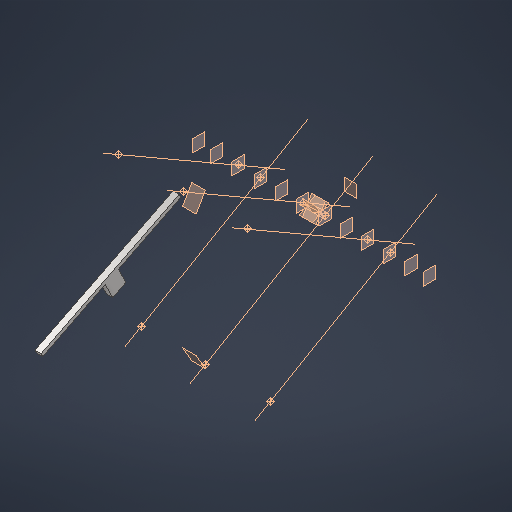
# Autodesk Inventor part: Chain_Tensioner_SIMPLIFIED
Saved by Autodesk Inventor 2027.1 (Build 311270010, 270A)
## iProperties
Created: 2026-10-17
Part Number: Chain_Tensioner_SIMPLIFIED
Material: Steel, Carbon
Document SubType Name: Modeling
Designer: kashyap
Density: 7.85 g/cm^3
Appearance: Semi-Polished
Material_Status: Assumed for this reconstruction
Author: kashyap
Autodesk Inventor part; units mm, degrees
ref_plane "YZ Plane" through (0, 0, 0) normal (1, 0, 0) x (0, 1, 0)
derived "V6_Engine_Master.ipt"
ref_plane "Bank_A_Plane" through (0, 0, 0) normal (0, 0.8660254, -0.5) x (-1, 0, 0)
ref_plane "Bank_B_Plane" through (0, 0, 0) normal (0, 0.8660254, 0.5) x (-1, 0, 0)
ref_plane "Bank_A_Perp_Plane" through (0, 0, 0) normal (0, 0.5, 0.8660254) x (-1, 0, 0)
ref_plane "Bank_B_Perp_Plane" through (0, 0, 0) normal (0, -0.5, 0.8660254) x (-1, 0, 0)
ref_plane "Bank_A_Deck_Plane" through (0, 112.9, 195.5485) normal (0, 0.5, 0.8660254) x (-1, 0, 0)
ref_plane "Bank_B_Deck_Plane" through (0, -112.9, 195.5485) normal (0, -0.5, 0.8660254) x (-1, 0, 0)
ref_plane "Cyl_A1_Station_Plane" through (-123.8, 0, 0) normal (1, 0, 0) x (0, 1, 0)
ref_plane "Cyl_A2_Station_Plane" through (-18.3, 0, 0) normal (1, 0, 0) x (0, 1, 0)
ref_plane "Cyl_A3_Station_Plane" through (87.2, 0, 0) normal (1, 0, 0) x (0, 1, 0)
ref_plane "Cyl_B1_Station_Plane" through (-87.2, 0, 0) normal (1, 0, 0) x (0, 1, 0)
ref_plane "Cyl_B2_Station_Plane" through (18.3, 0, 0) normal (1, 0, 0) x (0, 1, 0)
ref_plane "Cyl_B3_Station_Plane" through (123.8, 0, 0) normal (1, 0, 0) x (0, 1, 0)
ref_plane "Main_Bearing_Station_1" through (-158.25, 0, 0) normal (1, 0, 0) x (0, 1, 0)
ref_plane "Main_Bearing_Station_2" through (-52.75, 0, 0) normal (1, 0, 0) x (0, 1, 0)
ref_plane "Main_Bearing_Station_3" through (52.75, 0, 0) normal (1, 0, 0) x (0, 1, 0)
ref_plane "Main_Bearing_Station_4" through (158.25, 0, 0) normal (1, 0, 0) x (0, 1, 0)
ref_plane "Front_Interface" through (-188.25, 0, 0) normal (1, 0, 0) x (0, 1, 0)
ref_plane "Rear_Interface" through (188.25, 0, 0) normal (1, 0, 0) x (0, 1, 0)
ref_plane "Oil_Pan_Plane" through (0, 0, -60) normal (0, 0, 1) x (1, 0, 0)
ref_plane "Primary_Sprocket_Plane" through (-193.75, 0, 0) normal (1, 0, 0) x (0, 1, 0)
ref_plane "Secondary_Sprocket_Plane" through (-203.75, 0, 0) normal (1, 0, 0) x (0, 1, 0)
sketch "SK_Shoe" plane through (-193.75, 0, 0) normal (1, 0, 0) x (0, 1, 0)
  line L0 (-170.5132, 256.2107) -> (-58.2916, 30.8573)
  line L1 (-58.2916, 30.8573) -> (-63.6625, 28.1827)
  line L2 (-63.6625, 28.1827) -> (-175.8841, 253.5361)
  line L3 (-175.8841, 253.5361) -> (-170.5132, 256.2107)
  constraints: 8 end point
extrude "Shoe_SIMPLIFIED" add sketch "SK_Shoe" along normal mid plane 10
sketch "SK_Tensioner_Body" plane through (-193.75, 0, 0) normal (1, 0, 0) x (0, 1, 0)
  line L0 (-125.1225, 151.6012) -> (-114.4241, 130.1176)
  line L1 (-114.4241, 130.1176) -> (-139.0407, 117.859)
  line L2 (-139.0407, 117.859) -> (-149.7391, 139.3426)
  line L3 (-149.7391, 139.3426) -> (-125.1225, 151.6012)
  constraints: 8 end point
extrude "Tensioner_Body_SIMPLIFIED" add sketch "SK_Tensioner_Body" along normal mid plane 10
body "Solid2"
